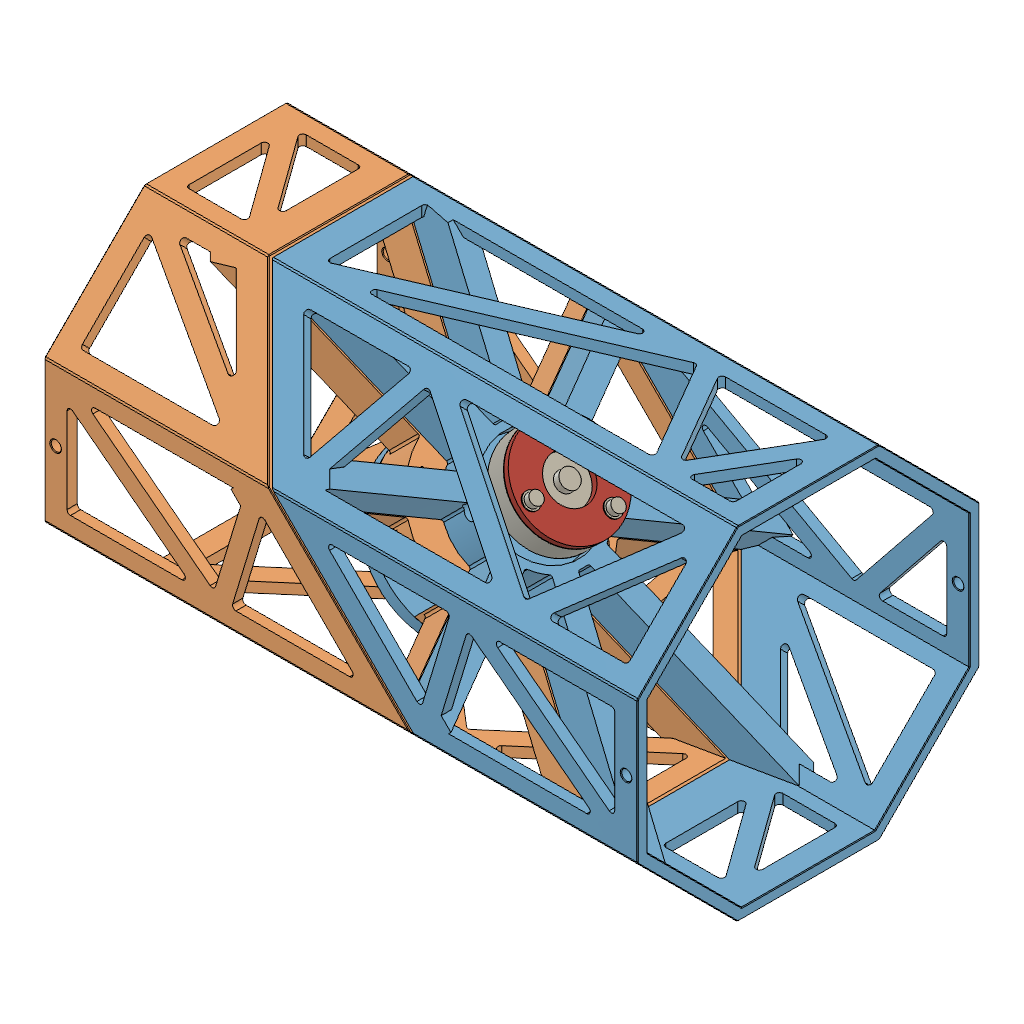
11-hardware-and-shaft (Autodesk Fusion 360 design; units mm, degrees)
part number: 2026-11-02-20-17-55-344
part number: 2026-11-02-20-17-59-218
part number: 2026-11-02-20-17-59-224
part number: 2026-11-02-20-19-00-695
part number: 2026-11-02-20-19-03-009
part number: 2026-11-02-20-19-04-949
part number: 2026-11-02-20-19-06-912
part number: 2026-11-02-20-19-11-903
part number: 2026-11-02-20-19-12-666
part number: 2026-11-02-20-19-12-978
part number: 2026-11-02-20-19-13-740
part number: 2026-11-02-20-19-14-532
part number: 2026-11-02-20-19-15-361
part number: 2026-11-02-20-19-17-468
part number: 2026-11-02-20-19-19-583
part number: 2026-11-02-20-19-25-638
part number: 2026-11-02-20-19-39-091
Autodesk Fusion 360 part; units mm, degrees
(part 1 of 8)
sketch "01 Master Octagon" plane through (0, 0, 0) normal (1, 0, 0) x (0, 0, -1)
  line L0 (75, 31.066) -> (31.066, 75)
  line L1 (31.066, 75) -> (-31.066, 75)
  line L2 (-31.066, 75) -> (-75, 31.066)
  line L3 (-75, 31.066) -> (-75, -31.066)
  line L4 (-75, -31.066) -> (-31.066, -75)
  line L5 (-31.066, -75) -> (31.066, -75)
  line L6 (31.066, -75) -> (75, -31.066)
  line L7 (75, -31.066) -> (75, 31.066)
  dimension "d59" = 150
  constraint horizontal L1
  measures "d59" vertical distance of L0.end L5.end
extrude "02 Symmetric Master Blank" add sketch "01 Master Octagon" along normal mid plane 260 makes body 1
ref_plane "WorkPlane1" through (0, 0, 12.125) normal (0.707107, 0.707107, 0) x (0, 0, 1)
split "03 Split at45 degrees" by plane through (0, 0, 12.125) normal (0.707107, 0.707107, 0) bodies 1 makes body 2 at (130, -10.3553, -25)
move_face "04 Half Gap Recess" offset -0.5 1 faces at (10.3553, -10.3553, -25) on bodies 2
move_face "04 Half Gap Recess (1)" offset -0.5 1 faces at (10.3553, -10.3553, -25) on bodies 1
copy_body "Body->Comp1" bodies 2 removing the originals makes body 3 in component "A Housing"
copy_body "Body->Comp2" bodies 1 removing the originals makes body 4 in component "B Moving Body"
shell "A Shell Open Both Ends" thickness 4.5 removed faces 2 at (-9.6482, 10.3553, -25) at (130, -10.3553, -25) on bodies 3 in component "A Housing"
shell "B Shell Open Both Ends" thickness 4.5 removed faces 2 at (-130, -10.3553, -25) at (-11.0624, 10.3553, -25) on bodies 4 in component "B Moving Body"
ref_plane "WorkPlane1" through (12.125, 0, 0) normal (0, 1, 0) x (1, 0, 0) in component "A Housing"
ref_plane "WorkPlane2" through (12.125, 75, 0) normal (0, 1, 0) x (1, 0, 0) in component "A Housing"
sketch "A Facet 0 Triangle 1" plane through (0, 75, 0) normal (0, 1, 0) x (1, 0, 0) in component "A Housing"
  line L0 (-65.1005, 27.066) -> (-65.1005, -27.066) construction
  line L1 (-65.1005, -27.066) -> (60.9665, 27.066) construction
  line L2 (60.9665, 27.066) -> (-65.1005, 27.066) construction
  line L3 (-61.1005, 23.066) -> (-61.1005, -20.9953)
  line L4 (-61.1005, -20.9953) -> (41.513, 23.066)
  line L5 (41.513, 23.066) -> (-61.1005, 23.066)
  dimension "d72" = 65.1005
  dimension "d73" = 27.066
  dimension "d74" = 65.1005
  dimension "d75" = 27.066
  dimension "d76" = 60.9665
  dimension "d77" = 27.066
  dimension "d78" = -4
  measures "d72" horizontal distance of origin L0.start
  measures "d73" vertical distance of origin L0.start
  measures "d74" horizontal distance of origin L0.end
  measures "d75" vertical distance of origin L0.end
  measures "d76" horizontal distance of origin L1.end
  measures "d77" vertical distance of origin L1.end
extrude "A Facet 0 Opening 1" cut sketch "A Facet 0 Triangle 1" against normal blind 4.7 bodies 3 in component "A Housing"
sketch "A Facet 0 Triangle 2" plane through (0, 75, 0) normal (0, 1, 0) x (1, 0, 0) in component "A Housing"
  line L0 (-65.1005, -27.066) -> (60.9665, 27.066) construction
  line L1 (60.9665, 27.066) -> (92.4832, -27.066) construction
  line L2 (92.4832, -27.066) -> (-65.1005, -27.066) construction
  line L3 (-45.647, -23.066) -> (59.2912, 21.9935)
  line L4 (59.2912, 21.9935) -> (85.5258, -23.066)
  line L5 (85.5258, -23.066) -> (-45.647, -23.066)
  dimension "d81" = 65.1005
  dimension "d82" = 27.066
  dimension "d83" = 60.9665
  dimension "d84" = 27.066
  dimension "d85" = 92.4832
  dimension "d86" = 27.066
  dimension "d87" = 4
  measures "d81" horizontal distance of origin L0.start
  measures "d82" vertical distance of origin L0.start
  measures "d83" horizontal distance of origin L0.end
  measures "d84" vertical distance of origin L0.end
  measures "d85" horizontal distance of origin L1.end
  measures "d86" vertical distance of origin L1.end
extrude "A Facet 0 Opening 2" cut sketch "A Facet 0 Triangle 2" against normal blind 4.7 bodies 3 in component "A Housing"
sketch "A Facet 0 Triangle 3" plane through (0, 75, 0) normal (0, 1, 0) x (1, 0, 0) in component "A Housing"
  line L0 (60.9665, 27.066) -> (92.4832, -27.066) construction
  line L1 (92.4832, -27.066) -> (124, 27.066) construction
  line L2 (124, 27.066) -> (60.9665, 27.066) construction
  line L3 (67.924, 23.066) -> (92.4832, -19.1161)
  line L4 (92.4832, -19.1161) -> (117.0425, 23.066)
  line L5 (117.0425, 23.066) -> (67.924, 23.066)
  dimension "d90" = 60.9665
  dimension "d91" = 27.066
  dimension "d92" = 92.4832
  dimension "d93" = 27.066
  dimension "d94" = 124
  dimension "d95" = 27.066
  dimension "d96" = -4
  measures "d90" horizontal distance of origin L0.start
  measures "d91" vertical distance of origin L0.start
  measures "d92" horizontal distance of origin L0.end
  measures "d93" vertical distance of origin L0.end
  measures "d94" horizontal distance of origin L1.end
  measures "d95" vertical distance of origin L1.end
extrude "A Facet 0 Opening 3" cut sketch "A Facet 0 Triangle 3" against normal blind 4.7 bodies 3 in component "A Housing"
sketch "A Facet 0 Triangle 4" plane through (0, 75, 0) normal (0, 1, 0) x (1, 0, 0) in component "A Housing"
  line L0 (92.4832, -27.066) -> (124, 27.066) construction
  line L1 (124, 27.066) -> (124, -27.066) construction
  line L2 (124, -27.066) -> (92.4832, -27.066) construction
  line L3 (99.4407, -23.066) -> (120, 12.2459)
  line L4 (120, 12.2459) -> (120, -23.066)
  line L5 (120, -23.066) -> (99.4407, -23.066)
  dimension "d99" = 92.4832
  dimension "d100" = 27.066
  dimension "d101" = 124
  dimension "d102" = 27.066
  dimension "d103" = 124
  dimension "d104" = 27.066
  dimension "d105" = 4
  measures "d99" horizontal distance of origin L0.start
  measures "d100" vertical distance of origin L0.start
  measures "d101" horizontal distance of origin L0.end
  measures "d102" vertical distance of origin L0.end
  measures "d103" horizontal distance of origin L1.end
  measures "d104" vertical distance of origin L1.end
extrude "A Facet 0 Opening 4" cut sketch "A Facet 0 Triangle 4" against normal blind 4.7 bodies 3 in component "A Housing"
fillet "A Facet 0 Aperture Root Radii" radius 1.5 12 edges at (120, 72.75, 23.066) (120, 72.75, -12.2459) (99.4407, 72.75, 23.066) (117.0425, 72.75, -23.066) (67.924, 72.75, -23.066) (92.4832, 72.75, 19.1161) (85.5258, 72.75, 23.066) (59.2912, 72.75, -21.9935) (-45.647, 72.75, 23.066) (41.513, 72.75, -23.066) (-61.1005, 72.75, -23.066) (-61.1005, 72.75, 20.9953) on bodies 3 in component "A Housing"
ref_plane "WorkPlane3" through (12.125, 0, 0) normal (0, 0.707107, 0.707107) x (1, 0, 0) in component "A Housing"
ref_plane "WorkPlane4" through (12.125, 53.033, 53.033) normal (0, 0.707107, 0.707107) x (1, 0, 0) in component "A Housing"
sketch "A Facet 45 Triangle 1" plane through (0, 53.033, 53.033) normal (0, 0.707107, 0.707107) x (1, 0, 0) in component "A Housing"
  line L0 (-62.2721, 27.066) -> (-23.9949, -27.066) construction
  line L1 (-23.9949, -27.066) -> (-0.1814, 27.066) construction
  line L2 (-0.1814, 27.066) -> (-62.2721, 27.066) construction
  line L3 (-54.5447, 23.066) -> (-24.81, -18.9852)
  line L4 (-24.81, -18.9852) -> (-6.311, 23.066)
  line L5 (-6.311, 23.066) -> (-54.5447, 23.066)
  dimension "d114" = 62.2721
  dimension "d115" = 27.066
  dimension "d116" = 23.9949
  dimension "d117" = 27.066
  dimension "d118" = 0.1814
  dimension "d119" = 27.066
  dimension "d120" = -4
  measures "d114" horizontal distance of origin L0.start
  measures "d115" vertical distance of origin L0.start
  measures "d116" horizontal distance of origin L0.end
  measures "d117" vertical distance of origin L0.end
  measures "d118" horizontal distance of origin L1.end
  measures "d119" vertical distance of origin L1.end
extrude "A Facet 45 Opening 1" cut sketch "A Facet 45 Triangle 1" against normal blind 4.7 bodies 3 in component "A Housing"
sketch "A Facet 45 Triangle 2" plane through (0, 53.033, 53.033) normal (0, 0.707107, 0.707107) x (1, 0, 0) in component "A Housing"
  line L0 (-23.9949, -27.066) -> (-0.1814, 27.066) construction
  line L1 (-0.1814, 27.066) -> (74.6684, -27.066) construction
  line L2 (74.6684, -27.066) -> (-23.9949, -27.066) construction
  line L3 (-17.8653, -23.066) -> (1.4863, 20.9235)
  line L4 (1.4863, 20.9235) -> (62.3117, -23.066)
  line L5 (62.3117, -23.066) -> (-17.8653, -23.066)
  dimension "d123" = 23.9949
  dimension "d124" = 27.066
  dimension "d125" = 0.1814
  dimension "d126" = 27.066
  dimension "d127" = 74.6684
  dimension "d128" = 27.066
  dimension "d129" = 4
  measures "d123" horizontal distance of origin L0.start
  measures "d124" vertical distance of origin L0.start
  measures "d125" horizontal distance of origin L0.end
  measures "d126" vertical distance of origin L0.end
  measures "d127" horizontal distance of origin L1.end
  measures "d128" vertical distance of origin L1.end
extrude "A Facet 45 Opening 2" cut sketch "A Facet 45 Triangle 2" against normal blind 4.7 bodies 3 in component "A Housing"
sketch "A Facet 45 Triangle 3" plane through (0, 53.033, 53.033) normal (0, 0.707107, 0.707107) x (1, 0, 0) in component "A Housing"
  line L0 (-0.1814, 27.066) -> (74.6684, -27.066) construction
  line L1 (74.6684, -27.066) -> (124, 27.066) construction
  line L2 (124, 27.066) -> (-0.1814, 27.066) construction
  line L3 (12.1753, 23.066) -> (74.1179, -21.7315)
  line L4 (74.1179, -21.7315) -> (114.9429, 23.066)
  line L5 (114.9429, 23.066) -> (12.1753, 23.066)
  dimension "d132" = 0.1814
  dimension "d133" = 27.066
  dimension "d134" = 74.6684
  dimension "d135" = 27.066
  dimension "d136" = 124
  dimension "d137" = 27.066
  dimension "d138" = -4
  measures "d132" horizontal distance of origin L0.start
  measures "d133" vertical distance of origin L0.start
  measures "d134" horizontal distance of origin L0.end
  measures "d135" vertical distance of origin L0.end
  measures "d136" horizontal distance of origin L1.end
  measures "d137" vertical distance of origin L1.end
extrude "A Facet 45 Opening 3" cut sketch "A Facet 45 Triangle 3" against normal blind 4.7 bodies 3 in component "A Housing"
sketch "A Facet 45 Triangle 4" plane through (0, 53.033, 53.033) normal (0, 0.707107, 0.707107) x (1, 0, 0) in component "A Housing"
  line L0 (74.6684, -27.066) -> (124, 27.066) construction
  line L1 (124, 27.066) -> (124, -27.066) construction
  line L2 (124, -27.066) -> (74.6684, -27.066) construction
  line L3 (83.7255, -23.066) -> (120, 16.7383)
  line L4 (120, 16.7383) -> (120, -23.066)
  line L5 (120, -23.066) -> (83.7255, -23.066)
  dimension "d141" = 74.6684
  dimension "d142" = 27.066
  dimension "d143" = 124
  dimension "d144" = 27.066
  dimension "d145" = 124
  dimension "d146" = 27.066
  dimension "d147" = 4
  measures "d141" horizontal distance of origin L0.start
  measures "d142" vertical distance of origin L0.start
  measures "d143" horizontal distance of origin L0.end
  measures "d144" vertical distance of origin L0.end
  measures "d145" horizontal distance of origin L1.end
  measures "d146" vertical distance of origin L1.end
extrude "A Facet 45 Opening 4" cut sketch "A Facet 45 Triangle 4" against normal blind 4.7 bodies 3 in component "A Housing"
fillet "A Facet 45 Aperture Root Radii" radius 1.5 12 edges at (120, 35.1319, 67.7522) (120, 63.2778, 39.6062) (83.7255, 35.1319, 67.7522) (114.9429, 67.7522, 35.1319) (12.1753, 67.7522, 35.1319) (74.1179, 36.0755, 66.8085) (62.3117, 35.1319, 67.7522) (1.4863, 66.2371, 36.6469) (-17.8653, 35.1319, 67.7522) (-6.311, 67.7522, 35.1319) (-54.5447, 67.7522, 35.1319) (-24.81, 38.0175, 64.8666) on bodies 3 in component "A Housing"
ref_plane "WorkPlane5" through (12.125, 0, 0) normal (0, 0, 1) x (1, 0, 0) in component "A Housing"
ref_plane "WorkPlane6" through (12.125, 0, 75) normal (0, 0, 1) x (1, 0, 0) in component "A Housing"
sketch "A Facet 90 Triangle 1" plane through (0, 0, 75) normal (0, 0, 1) x (1, 0, 0) in component "A Housing"
  line L0 (-17.1665, 27.066) -> (36.9655, -27.066) construction
  line L1 (36.9655, -27.066) -> (53.4167, 27.066) construction
  line L2 (53.4167, 27.066) -> (-17.1665, 27.066) construction
  line L3 (-7.5097, 23.066) -> (35.0777, -19.5214)
  line L4 (35.0777, -19.5214) -> (48.0205, 23.066)
  line L5 (48.0205, 23.066) -> (-7.5097, 23.066)
  dimension "d156" = 17.1665
  dimension "d157" = 27.066
  dimension "d158" = 36.9655
  dimension "d159" = 27.066
  dimension "d160" = 53.4167
  dimension "d161" = 27.066
  dimension "d162" = -4
  measures "d156" horizontal distance of origin L0.start
  measures "d157" vertical distance of origin L0.start
  measures "d158" horizontal distance of origin L0.end
  measures "d159" vertical distance of origin L0.end
  measures "d160" horizontal distance of origin L1.end
  measures "d161" vertical distance of origin L1.end
extrude "A Facet 90 Opening 1" cut sketch "A Facet 90 Triangle 1" against normal blind 4.7 bodies 3 in component "A Housing"
sketch "A Facet 90 Triangle 2" plane through (0, 0, 75) normal (0, 0, 1) x (1, 0, 0) in component "A Housing"
  line L0 (36.9655, -27.066) -> (53.4167, 27.066) construction
  line L1 (53.4167, 27.066) -> (124, -27.066) construction
  line L2 (124, -27.066) -> (36.9655, -27.066) construction
  line L3 (42.3618, -23.066) -> (55.5648, 20.3777)
  line L4 (55.5648, 20.3777) -> (112.2115, -23.066)
  line L5 (112.2115, -23.066) -> (42.3618, -23.066)
  dimension "d165" = 36.9655
  dimension "d166" = 27.066
  dimension "d167" = 53.4167
  dimension "d168" = 27.066
  dimension "d169" = 124
  dimension "d170" = 27.066
  dimension "d171" = 4
  measures "d165" horizontal distance of origin L0.start
  measures "d166" vertical distance of origin L0.start
  measures "d167" horizontal distance of origin L0.end
  measures "d168" vertical distance of origin L0.end
  measures "d169" horizontal distance of origin L1.end
  measures "d170" vertical distance of origin L1.end
extrude "A Facet 90 Opening 2" cut sketch "A Facet 90 Triangle 2" against normal blind 4.7 bodies 3 in component "A Housing"
sketch "A Facet 90 Triangle 3" plane through (0, 0, 75) normal (0, 0, 1) x (1, 0, 0) in component "A Housing"
  line L0 (53.4167, 27.066) -> (124, -27.066) construction
  line L1 (124, -27.066) -> (124, 27.066) construction
  line L2 (124, 27.066) -> (53.4167, 27.066) construction
  line L3 (65.2053, 23.066) -> (120, -18.9574)
  line L4 (120, -18.9574) -> (120, 23.066)
  line L5 (120, 23.066) -> (65.2053, 23.066)
  dimension "d174" = 53.4167
  dimension "d175" = 27.066
  dimension "d176" = 124
  dimension "d177" = 27.066
  dimension "d178" = 124
  dimension "d179" = 27.066
  dimension "d180" = -4
  measures "d174" horizontal distance of origin L0.start
  measures "d175" vertical distance of origin L0.start
  measures "d176" horizontal distance of origin L0.end
  measures "d177" vertical distance of origin L0.end
  measures "d178" horizontal distance of origin L1.end
  measures "d179" vertical distance of origin L1.end
extrude "A Facet 90 Opening 3" cut sketch "A Facet 90 Triangle 3" against normal blind 4.7 bodies 3 in component "A Housing"
fillet "A Facet 90 Aperture Root Radii" radius 1.5 9 edges at (120, 23.066, 72.75) (65.2053, 23.066, 72.75) (120, -18.9574, 72.75) (112.2115, -23.066, 72.75) (55.5648, 20.3777, 72.75) (42.3618, -23.066, 72.75) (48.0205, 23.066, 72.75) (-7.5097, 23.066, 72.75) (35.0777, -19.5214, 72.75) on bodies 3 in component "A Housing"
ref_plane "WorkPlane7" through (12.125, 0, 0) normal (0, -0.707107, 0.707107) x (1, 0, 0) in component "A Housing"
ref_plane "WorkPlane8" through (12.125, -53.033, 53.033) normal (0, -0.707107, 0.707107) x (1, 0, 0) in component "A Housing"
sketch "A Facet 135 Triangle 1" plane through (0, -53.033, 53.033) normal (0, -0.707107, 0.707107) x (1, 0, 0) in component "A Housing"
  line L0 (43.7939, 27.066) -> (82.0711, -27.066) construction
  line L1 (82.0711, -27.066) -> (124, 27.066) construction
  line L2 (124, 27.066) -> (43.7939, 27.066) construction
  line L3 (51.5213, 23.066) -> (82.2175, -20.3449)
  line L4 (82.2175, -20.3449) -> (115.8422, 23.066)
  line L5 (115.8422, 23.066) -> (51.5213, 23.066)
  dimension "d189" = 43.7939
  dimension "d190" = 27.066
  dimension "d191" = 82.0711
  dimension "d192" = 27.066
  dimension "d193" = 124
  dimension "d194" = 27.066
  dimension "d195" = -4
  measures "d189" horizontal distance of origin L0.start
  measures "d190" vertical distance of origin L0.start
  measures "d191" horizontal distance of origin L0.end
  measures "d192" vertical distance of origin L0.end
  measures "d193" horizontal distance of origin L1.end
  measures "d194" vertical distance of origin L1.end
extrude "A Facet 135 Opening 1" cut sketch "A Facet 135 Triangle 1" against normal blind 4.7 bodies 3 in component "A Housing"
sketch "A Facet 135 Triangle 2" plane through (0, -53.033, 53.033) normal (0, -0.707107, 0.707107) x (1, 0, 0) in component "A Housing"
  line L0 (82.0711, -27.066) -> (124, 27.066) construction
  line L1 (124, 27.066) -> (124, -27.066) construction
  line L2 (124, -27.066) -> (82.0711, -27.066) construction
  line L3 (90.2289, -23.066) -> (120, 15.3697)
  line L4 (120, 15.3697) -> (120, -23.066)
  line L5 (120, -23.066) -> (90.2289, -23.066)
  dimension "d198" = 82.0711
  dimension "d199" = 27.066
  dimension "d200" = 124
  dimension "d201" = 27.066
  dimension "d202" = 124
  dimension "d203" = 27.066
  dimension "d204" = 4
  measures "d198" horizontal distance of origin L0.start
  measures "d199" vertical distance of origin L0.start
  measures "d200" horizontal distance of origin L0.end
  measures "d201" vertical distance of origin L0.end
  measures "d202" horizontal distance of origin L1.end
  measures "d203" vertical distance of origin L1.end
extrude "A Facet 135 Opening 2" cut sketch "A Facet 135 Triangle 2" against normal blind 4.7 bodies 3 in component "A Housing"
fillet "A Facet 135 Aperture Root Radii" radius 1.5 6 edges at (120, -67.7522, 35.1319) (120, -40.574, 62.3101) (90.2289, -67.7522, 35.1319) (115.8422, -35.1319, 67.7522) (51.5213, -35.1319, 67.7522) (82.2175, -65.828, 37.056) on bodies 3 in component "A Housing"
ref_plane "WorkPlane9" through (12.125, 0, 0) normal (0, -1, 0) x (1, 0, 0) in component "A Housing"
ref_plane "WorkPlane10" through (12.125, -75, 0) normal (0, -1, 0) x (1, 0, 0) in component "A Housing"
sketch "A Facet 180 Triangle 1" plane through (0, -75, 0) normal (0, -1, 0) x (-1, 0, 0) in component "A Housing"
  line L0 (-84.8995, -27.066) -> (-84.8995, 27.066) construction
  line L1 (-84.8995, 27.066) -> (-124, -27.066) construction
  line L2 (-124, -27.066) -> (-84.8995, -27.066) construction
  line L3 (-88.8995, -23.066) -> (-88.8995, 14.697)
  line L4 (-88.8995, 14.697) -> (-116.1764, -23.066)
  line L5 (-116.1764, -23.066) -> (-88.8995, -23.066)
  dimension "d213" = 84.8995
  dimension "d214" = 27.066
  dimension "d215" = 84.8995
  dimension "d216" = 27.066
  dimension "d217" = 124
  dimension "d218" = 27.066
  dimension "d219" = -4
  measures "d213" horizontal distance of origin L0.start
  measures "d214" vertical distance of origin L0.start
  measures "d215" horizontal distance of origin L0.end
  measures "d216" vertical distance of origin L0.end
  measures "d217" horizontal distance of origin L1.end
  measures "d218" vertical distance of origin L1.end
extrude "A Facet 180 Opening 1" cut sketch "A Facet 180 Triangle 1" against normal blind 4.7 bodies 3 in component "A Housing"
sketch "A Facet 180 Triangle 2" plane through (0, -75, 0) normal (0, -1, 0) x (-1, 0, 0) in component "A Housing"
  line L0 (-84.8995, 27.066) -> (-124, -27.066) construction
  line L1 (-124, -27.066) -> (-124, 27.066) construction
  line L2 (-124, 27.066) -> (-84.8995, 27.066) construction
  line L3 (-92.7231, 23.066) -> (-120, -14.697)
  line L4 (-120, -14.697) -> (-120, 23.066)
  line L5 (-120, 23.066) -> (-92.7231, 23.066)
  dimension "d222" = 84.8995
  dimension "d223" = 27.066
  dimension "d224" = 124
  dimension "d225" = 27.066
  dimension "d226" = 124
  dimension "d227" = 27.066
  dimension "d228" = 4
  measures "d222" horizontal distance of origin L0.start
  measures "d223" vertical distance of origin L0.start
  measures "d224" horizontal distance of origin L0.end
  measures "d225" vertical distance of origin L0.end
  measures "d226" horizontal distance of origin L1.end
  measures "d227" vertical distance of origin L1.end
extrude "A Facet 180 Opening 2" cut sketch "A Facet 180 Triangle 2" against normal blind 4.7 bodies 3 in component "A Housing"
fillet "A Facet 180 Aperture Root Radii" radius 1.5 6 edges at (120, -72.75, -23.066) (120, -72.75, 14.697) (92.7231, -72.75, -23.066) (116.1764, -72.75, 23.066) (88.8995, -72.75, 23.066) (88.8995, -72.75, -14.697) on bodies 3 in component "A Housing"
ref_plane "WorkPlane11" through (12.125, 0, 0) normal (0, -0.707107, -0.707107) x (1, 0, 0) in component "A Housing"
ref_plane "WorkPlane12" through (12.125, -53.033, -53.033) normal (0, -0.707107, -0.707107) x (1, 0, 0) in component "A Housing"
sketch "A Facet 225 Triangle 1" plane through (0, -53.033, -53.033) normal (0, -0.707107, -0.707107) x (1, 0, 0) in component "A Housing"
  line L0 (82.0711, 27.066) -> (43.7939, -27.066) construction
  line L1 (43.7939, -27.066) -> (124, 27.066) construction
  line L2 (124, 27.066) -> (82.0711, 27.066) construction
  line L3 (84.1416, 23.066) -> (59.6927, -11.51)
  line L4 (59.6927, -11.51) -> (110.9231, 23.066)
  line L5 (110.9231, 23.066) -> (84.1416, 23.066)
  dimension "d237" = 82.0711
  dimension "d238" = 27.066
  dimension "d239" = 43.7939
  dimension "d240" = 27.066
  dimension "d241" = 124
  dimension "d242" = 27.066
  dimension "d243" = -4
  measures "d237" horizontal distance of origin L0.start
  measures "d238" vertical distance of origin L0.start
  measures "d239" horizontal distance of origin L0.end
  measures "d240" vertical distance of origin L0.end
  measures "d241" horizontal distance of origin L1.end
  measures "d242" vertical distance of origin L1.end
extrude "A Facet 225 Opening 1" cut sketch "A Facet 225 Triangle 1" against normal blind 4.7 bodies 3 in component "A Housing"
sketch "A Facet 225 Triangle 2" plane through (0, -53.033, -53.033) normal (0, -0.707107, -0.707107) x (1, 0, 0) in component "A Housing"
  line L0 (43.7939, -27.066) -> (124, 27.066) construction
  line L1 (124, 27.066) -> (124, -27.066) construction
  line L2 (124, -27.066) -> (43.7939, -27.066) construction
  line L3 (56.8709, -23.066) -> (120, 19.5406)
  line L4 (120, 19.5406) -> (120, -23.066)
  line L5 (120, -23.066) -> (56.8709, -23.066)
  dimension "d246" = 43.7939
  dimension "d247" = 27.066
  dimension "d248" = 124
  dimension "d249" = 27.066
  dimension "d250" = 124
  dimension "d251" = 27.066
  dimension "d252" = 4
  measures "d246" horizontal distance of origin L0.start
  measures "d247" vertical distance of origin L0.start
  measures "d248" horizontal distance of origin L0.end
  measures "d249" vertical distance of origin L0.end
  measures "d250" horizontal distance of origin L1.end
  measures "d251" vertical distance of origin L1.end
extrude "A Facet 225 Opening 2" cut sketch "A Facet 225 Triangle 2" against normal blind 4.7 bodies 3 in component "A Housing"
fillet "A Facet 225 Aperture Root Radii" radius 1.5 6 edges at (120, -35.1319, -67.7522) (120, -65.2593, -37.6247) (56.8709, -35.1319, -67.7522) (110.9231, -67.7522, -35.1319) (84.1416, -67.7522, -35.1319) (59.6927, -43.3032, -59.5808) on bodies 3 in component "A Housing"
ref_plane "WorkPlane13" through (12.125, 0, 0) normal (0, 0, -1) x (1, 0, 0) in component "A Housing"
ref_plane "WorkPlane14" through (12.125, 0, -75) normal (0, 0, -1) x (1, 0, 0) in component "A Housing"
sketch "A Facet 270 Triangle 1" plane through (0, 0, -75) normal (0, 0, -1) x (-1, 0, 0) in component "A Housing"
  line L0 (-36.9655, -27.066) -> (17.1665, 27.066) construction
  line L1 (17.1665, 27.066) -> (-80.4828, -27.066) construction
  line L2 (-80.4828, -27.066) -> (-36.9655, -27.066) construction
  line L3 (-38.6224, -23.066) -> (-5.7896, 9.7668)
  line L4 (-5.7896, 9.7668) -> (-65.0169, -23.066)
  line L5 (-65.0169, -23.066) -> (-38.6224, -23.066)
  dimension "d261" = 36.9655
  dimension "d262" = 27.066
  dimension "d263" = 17.1665
  dimension "d264" = 27.066
  dimension "d265" = 80.4828
  dimension "d266" = 27.066
  dimension "d267" = -4
  measures "d261" horizontal distance of origin L0.start
  measures "d262" vertical distance of origin L0.start
  measures "d263" horizontal distance of origin L0.end
  measures "d264" vertical distance of origin L0.end
  measures "d265" horizontal distance of origin L1.end
  measures "d266" vertical distance of origin L1.end
extrude "A Facet 270 Opening 1" cut sketch "A Facet 270 Triangle 1" against normal blind 4.7 bodies 3 in component "A Housing"
sketch "A Facet 270 Triangle 2" plane through (0, 0, -75) normal (0, 0, -1) x (-1, 0, 0) in component "A Housing"
  line L0 (17.1665, 27.066) -> (-80.4828, -27.066) construction
  line L1 (-80.4828, -27.066) -> (-124, 27.066) construction
  line L2 (-124, 27.066) -> (17.1665, 27.066) construction
  line L3 (1.7007, 23.066) -> (-79.4759, -21.9343)
  line L4 (-79.4759, -21.9343) -> (-115.6521, 23.066)
  line L5 (-115.6521, 23.066) -> (1.7007, 23.066)
  dimension "d270" = 17.1665
  dimension "d271" = 27.066
  dimension "d272" = 80.4828
  dimension "d273" = 27.066
  dimension "d274" = 124
  dimension "d275" = 27.066
  dimension "d276" = 4
  measures "d270" horizontal distance of origin L0.start
  measures "d271" vertical distance of origin L0.start
  measures "d272" horizontal distance of origin L0.end
  measures "d273" vertical distance of origin L0.end
  measures "d274" horizontal distance of origin L1.end
  measures "d275" vertical distance of origin L1.end
extrude "A Facet 270 Opening 2" cut sketch "A Facet 270 Triangle 2" against normal blind 4.7 bodies 3 in component "A Housing"
sketch "A Facet 270 Triangle 3" plane through (0, 0, -75) normal (0, 0, -1) x (-1, 0, 0) in component "A Housing"
  line L0 (-80.4828, -27.066) -> (-124, 27.066) construction
  line L1 (-124, 27.066) -> (-124, -27.066) construction
  line L2 (-124, -27.066) -> (-80.4828, -27.066) construction
  line L3 (-88.8307, -23.066) -> (-120, 15.7062)
  line L4 (-120, 15.7062) -> (-120, -23.066)
  line L5 (-120, -23.066) -> (-88.8307, -23.066)
  dimension "d279" = 80.4828
  dimension "d280" = 27.066
  dimension "d281" = 124
  dimension "d282" = 27.066
  dimension "d283" = 124
  dimension "d284" = 27.066
  dimension "d285" = -4
  measures "d279" horizontal distance of origin L0.start
  measures "d280" vertical distance of origin L0.start
  measures "d281" horizontal distance of origin L0.end
  measures "d282" vertical distance of origin L0.end
  measures "d283" horizontal distance of origin L1.end
  measures "d284" vertical distance of origin L1.end
extrude "A Facet 270 Opening 3" cut sketch "A Facet 270 Triangle 3" against normal blind 4.7 bodies 3 in component "A Housing"
fillet "A Facet 270 Aperture Root Radii" radius 1.5 9 edges at (120, -23.066, -72.75) (88.8307, -23.066, -72.75) (120, 15.7062, -72.75) (115.6521, 23.066, -72.75) (79.4759, -21.9343, -72.75) (-1.7007, 23.066, -72.75) (65.0169, -23.066, -72.75) (38.6224, -23.066, -72.75) (5.7896, 9.7668, -72.75) on bodies 3 in component "A Housing"
ref_plane "WorkPlane15" through (12.125, 0, 0) normal (0, 0.707107, -0.707107) x (1, 0, 0) in component "A Housing"
ref_plane "WorkPlane16" through (12.125, 53.033, -53.033) normal (0, 0.707107, -0.707107) x (1, 0, 0) in component "A Housing"
sketch "A Facet 315 Triangle 1" plane through (0, 53.033, -53.033) normal (0, 0.707107, -0.707107) x (1, 0, 0) in component "A Housing"
  line L0 (-23.9949, 27.066) -> (-62.2721, -27.066) construction
  line L1 (-62.2721, -27.066) -> (25.3367, 27.066) construction
  line L2 (25.3367, 27.066) -> (-23.9949, 27.066) construction
  line L3 (-21.9244, 23.066) -> (-47.6674, -13.34)
  line L4 (-47.6674, -13.34) -> (11.2532, 23.066)
  line L5 (11.2532, 23.066) -> (-21.9244, 23.066)
  dimension "d294" = 23.9949
  dimension "d295" = 27.066
  dimension "d296" = 62.2721
  dimension "d297" = 27.066
  dimension "d298" = 25.3367
  dimension "d299" = 27.066
  dimension "d300" = -4
  measures "d294" horizontal distance of origin L0.start
  measures "d295" vertical distance of origin L0.start
  measures "d296" horizontal distance of origin L0.end
  measures "d297" vertical distance of origin L0.end
  measures "d298" horizontal distance of origin L1.end
  measures "d299" vertical distance of origin L1.end
extrude "A Facet 315 Opening 1" cut sketch "A Facet 315 Triangle 1" against normal blind 4.7 bodies 3 in component "A Housing"
sketch "A Facet 315 Triangle 2" plane through (0, 53.033, -53.033) normal (0, 0.707107, -0.707107) x (1, 0, 0) in component "A Housing"
  line L0 (-62.2721, -27.066) -> (25.3367, 27.066) construction
  line L1 (25.3367, 27.066) -> (61.9093, -27.066) construction
  line L2 (61.9093, -27.066) -> (-62.2721, -27.066) construction
  line L3 (-48.1886, -23.066) -> (24.1722, 21.6445)
  line L4 (24.1722, 21.6445) -> (54.3795, -23.066)
  line L5 (54.3795, -23.066) -> (-48.1886, -23.066)
  dimension "d303" = 62.2721
  dimension "d304" = 27.066
  dimension "d305" = 25.3367
  dimension "d306" = 27.066
  dimension "d307" = 61.9093
  dimension "d308" = 27.066
  dimension "d309" = 4
  measures "d303" horizontal distance of origin L0.start
  measures "d304" vertical distance of origin L0.start
  measures "d305" horizontal distance of origin L0.end
  measures "d306" vertical distance of origin L0.end
  measures "d307" horizontal distance of origin L1.end
  measures "d308" vertical distance of origin L1.end
extrude "A Facet 315 Opening 2" cut sketch "A Facet 315 Triangle 2" against normal blind 4.7 bodies 3 in component "A Housing"
sketch "A Facet 315 Triangle 3" plane through (0, 53.033, -53.033) normal (0, 0.707107, -0.707107) x (1, 0, 0) in component "A Housing"
  line L0 (25.3367, 27.066) -> (61.9093, -27.066) construction
  line L1 (61.9093, -27.066) -> (124, 27.066) construction
  line L2 (124, 27.066) -> (25.3367, 27.066) construction
  line L3 (32.8665, 23.066) -> (62.6909, -21.0779)
  line L4 (62.6909, -21.0779) -> (113.325, 23.066)
  line L5 (113.325, 23.066) -> (32.8665, 23.066)
  dimension "d312" = 25.3367
  dimension "d313" = 27.066
  dimension "d314" = 61.9093
  dimension "d315" = 27.066
  dimension "d316" = 124
  dimension "d317" = 27.066
  dimension "d318" = -4
  measures "d312" horizontal distance of origin L0.start
  measures "d313" vertical distance of origin L0.start
  measures "d314" horizontal distance of origin L0.end
  measures "d315" vertical distance of origin L0.end
  measures "d316" horizontal distance of origin L1.end
  measures "d317" vertical distance of origin L1.end
extrude "A Facet 315 Opening 3" cut sketch "A Facet 315 Triangle 3" against normal blind 4.7 bodies 3 in component "A Housing"
sketch "A Facet 315 Triangle 4" plane through (0, 53.033, -53.033) normal (0, 0.707107, -0.707107) x (1, 0, 0) in component "A Housing"
  line L0 (61.9093, -27.066) -> (124, 27.066) construction
  line L1 (124, 27.066) -> (124, -27.066) construction
  line L2 (124, -27.066) -> (61.9093, -27.066) construction
  line L3 (72.5843, -23.066) -> (120, 18.272)
  line L4 (120, 18.272) -> (120, -23.066)
  line L5 (120, -23.066) -> (72.5843, -23.066)
  dimension "d321" = 61.9093
  dimension "d322" = 27.066
  dimension "d323" = 124
  dimension "d324" = 27.066
  dimension "d325" = 124
  dimension "d326" = 27.066
  dimension "d327" = 4
  measures "d321" horizontal distance of origin L0.start
  measures "d322" vertical distance of origin L0.start
  measures "d323" horizontal distance of origin L0.end
  measures "d324" vertical distance of origin L0.end
  measures "d325" horizontal distance of origin L1.end
  measures "d326" vertical distance of origin L1.end
extrude "A Facet 315 Opening 4" cut sketch "A Facet 315 Triangle 4" against normal blind 4.7 bodies 3 in component "A Housing"
fillet "A Facet 315 Aperture Root Radii" radius 1.5 12 edges at (120, 67.7522, -35.1319) (120, 38.5218, -64.3623) (72.5843, 67.7522, -35.1319) (113.325, 35.1319, -67.7522) (32.8665, 35.1319, -67.7522) (62.6909, 66.3463, -36.5377) (54.3795, 67.7522, -35.1319) (24.1722, 36.137, -66.747) (-48.1886, 67.7522, -35.1319) (11.2532, 35.1319, -67.7522) (-21.9244, 35.1319, -67.7522) (-47.6674, 60.8748, -42.0092) on bodies 3 in component "A Housing"
ref_plane "WorkPlane1" through (12.125, 0, 0) normal (0, 1, 0) x (1, 0, 0) in component "B Moving Body"
ref_plane "WorkPlane2" through (12.125, 75, 0) normal (0, 1, 0) x (1, 0, 0) in component "B Moving Body"
sketch "B Facet 0 Triangle 1" plane through (0, 75, 0) normal (0, 1, 0) x (1, 0, 0) in component "B Moving Body"
  line L0 (-84.8995, 27.066) -> (-84.8995, -27.066) construction
  line L1 (-84.8995, -27.066) -> (-124, 27.066) construction
  line L2 (-124, 27.066) -> (-84.8995, 27.066) construction
  line L3 (-88.8995, 23.066) -> (-88.8995, -14.697)
  line L4 (-88.8995, -14.697) -> (-116.1764, 23.066)
  line L5 (-116.1764, 23.066) -> (-88.8995, 23.066)
  dimension "d336" = 84.8995
  dimension "d337" = 27.066
  dimension "d338" = 84.8995
  dimension "d339" = 27.066
  dimension "d340" = 124
  dimension "d341" = 27.066
  dimension "d342" = 4
  measures "d336" horizontal distance of origin L0.start
  measures "d337" vertical distance of origin L0.start
  measures "d338" horizontal distance of origin L0.end
  measures "d339" vertical distance of origin L0.end
  measures "d340" horizontal distance of origin L1.end
  measures "d341" vertical distance of origin L1.end
extrude "B Facet 0 Opening 1" cut sketch "B Facet 0 Triangle 1" against normal blind 4.7 bodies 4 in component "B Moving Body"
sketch "B Facet 0 Triangle 2" plane through (0, 75, 0) normal (0, 1, 0) x (1, 0, 0) in component "B Moving Body"
  line L0 (-84.8995, -27.066) -> (-124, 27.066) construction
  line L1 (-124, 27.066) -> (-124, -27.066) construction
  line L2 (-124, -27.066) -> (-84.8995, -27.066) construction
  line L3 (-92.7231, -23.066) -> (-120, 14.697)
  line L4 (-120, 14.697) -> (-120, -23.066)
  line L5 (-120, -23.066) -> (-92.7231, -23.066)
  dimension "d345" = 84.8995
  dimension "d346" = 27.066
  dimension "d347" = 124
  dimension "d348" = 27.066
  dimension "d349" = 124
  dimension "d350" = 27.066
  dimension "d351" = -4
  measures "d345" horizontal distance of origin L0.start
  measures "d346" vertical distance of origin L0.start
  measures "d347" horizontal distance of origin L0.end
  measures "d348" vertical distance of origin L0.end
  measures "d349" horizontal distance of origin L1.end
  measures "d350" vertical distance of origin L1.end
extrude "B Facet 0 Opening 2" cut sketch "B Facet 0 Triangle 2" against normal blind 4.7 bodies 4 in component "B Moving Body"
fillet "B Facet 0 Aperture Root Radii" radius 1.5 6 edges at (-120, 72.75, 23.066) (-92.7231, 72.75, 23.066) (-120, 72.75, -14.697) (-116.1764, 72.75, -23.066) (-88.8995, 72.75, 14.697) (-88.8995, 72.75, -23.066) on bodies 4 in component "B Moving Body"
ref_plane "WorkPlane3" through (12.125, 0, 0) normal (0, 0.707107, 0.707107) x (1, 0, 0) in component "B Moving Body"
ref_plane "WorkPlane4" through (12.125, 53.033, 53.033) normal (0, 0.707107, 0.707107) x (1, 0, 0) in component "B Moving Body"
sketch "B Facet 45 Triangle 1" plane through (0, 53.033, 53.033) normal (0, 0.707107, 0.707107) x (1, 0, 0) in component "B Moving Body"
  line L0 (-82.0711, 27.066) -> (-43.7939, -27.066) construction
  line L1 (-43.7939, -27.066) -> (-124, 27.066) construction
  line L2 (-124, 27.066) -> (-82.0711, 27.066) construction
  line L3 (-84.1416, 23.066) -> (-59.6927, -11.51)
  line L4 (-59.6927, -11.51) -> (-110.9231, 23.066)
  line L5 (-110.9231, 23.066) -> (-84.1416, 23.066)
  dimension "d360" = 82.0711
  dimension "d361" = 27.066
  dimension "d362" = 43.7939
  dimension "d363" = 27.066
  dimension "d364" = 124
  dimension "d365" = 27.066
  dimension "d366" = 4
  measures "d360" horizontal distance of origin L0.start
  measures "d361" vertical distance of origin L0.start
  measures "d362" horizontal distance of origin L0.end
  measures "d363" vertical distance of origin L0.end
  measures "d364" horizontal distance of origin L1.end
  measures "d365" vertical distance of origin L1.end
extrude "B Facet 45 Opening 1" cut sketch "B Facet 45 Triangle 1" against normal blind 4.7 bodies 4 in component "B Moving Body"